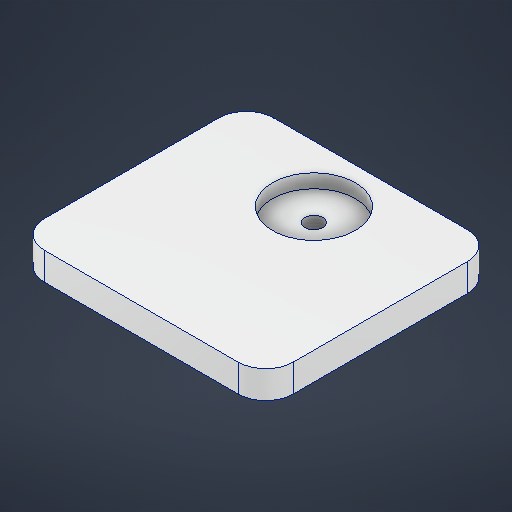
# Autodesk Inventor part: Base plate (Final Project)
Saved by Autodesk Inventor 2026 (Build 300175000, 175)
## iProperties
Created: 2025-12-01
Part Number: Base plate (Final Project)
Material: Aluminum 6061
Document SubType Name: Modeling
Designer: gmz
Density: 2.7 g/cm^3
Appearance: Aluminum - Flat
Author: gmz
Autodesk Inventor part; units mm, degrees
ref_plane "YZ Plane" through (0, 0, 0) normal (1, 0, 0) x (0, 1, 0)
ref_plane "XZ Plane" through (0, 0, 0) normal (0, 1, 0) x (-1, 0, 0)
ref_plane "XY Plane" through (0, 0, 0) normal (0, 0, 1) x (1, 0, 0)
sketch "Sketch1" plane through (0, 0, 0) normal (0, 1, 0) x (-1, 0, 0)
  line L0 (-95.1817, -294.0901) -> (-323.7817, -294.0901)
  line L1 (-323.7817, -294.0901) -> (-323.7817, -83.2701)
  line L2 (-323.7817, -83.2701) -> (-95.1817, -83.2701)
  line L3 (-95.1817, -83.2701) -> (-95.1817, -294.0901)
  point P0 (0, 0)
  dimension "d0" = 228.6
  dimension "d1" = 210.82
  constraints: 8 end point, 2 parallel, 1 horizontal, 1 perpendicular
  measures "d0" distance of L1.end L2.end
  measures "d1" distance of L2.end L0.start
extrude "Extrusion1" add sketch "Sketch1" along normal blind 25.4
sketch "Sketch2" plane through (0, 25.4, 0) normal (0, 1, 0) x (1, 0, 0)
  line L0 (323.7817, 294.0901) -> (95.1817, 294.0901) projected
  circle A0 centre (209.4817, 241.8813) radius 38.1
  point P0 (0, 0)
  dimension "d5" = 76.2
  constraints: 1 centre point
  measures "d5" diameter of A0
extrude "Extrusion3" cut sketch "Sketch2" against normal blind 12.7
sketch "Sketch5" plane through (209.4817, 12.7, -241.8813) normal (0, 1, 0) x (1, 0, 0)
  circle A0 centre (0, 0) radius 9.525
  point P0 (-209.4817, -241.8813)
  dimension "d14" = 19.05
  constraints: 1 centre point
  measures "d14" diameter of A0
hole "Hole1" at (209.4817, 12.7, -241.8813) direction (0, -1, 0) diameter 16.3068 end through all thread size "3/4-10 UNC" class "2B" standard "ANSI Unified Screw Threads"
fillet "Fillet1" radius 25.4 4 edges at (95.1817, 12.7, -83.2701) (323.7817, 12.7, -83.2701) (323.7817, 12.7, -294.0901) (95.1817, 12.7, -294.0901)
body "Solid1"
